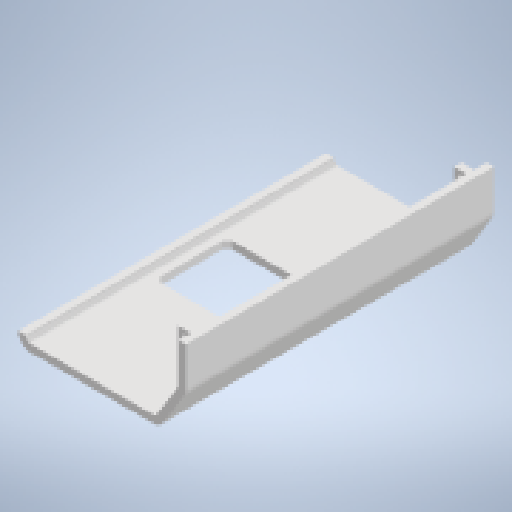
# Autodesk Inventor part: BoxTop3DPrint
Saved by Autodesk Inventor 2025.2 (Build 292293000, 293)
## iProperties
Created: 2025-06-26
Part Number: BoxTop3DPrint
Material: Generic
Document SubType Name: Modeling
Designer: ricoa
Density: 1 g/cm^3
Appearance: Default
Author: ricoa
Autodesk Inventor part; units mm, degrees
ref_plane "YZ Plane" through (0, 0, 0) normal (1, 0, 0) x (0, 1, 0)
ref_plane "XZ Plane" through (0, 0, 0) normal (0, 1, 0) x (-1, 0, 0)
sketch "Sketch1" plane through (0, 0, 0) normal (0, 0, 1) x (1, 0, 0)
  arc A0 (-33.75, -32) -> (-28.75, -37) centre (-28.75, -32) ccw projected
  line L0 (-28.75, -37) -> (20.4614, -37) projected
  line L1 (24.7154, -34.6275) -> (33.004, -21.2078) projected
  arc A1 (20.4614, -37) -> (24.7154, -34.6275) centre (20.4614, -32) ccw projected
  line L2 (33.75, -18.5804) -> (33.75, -3) projected
  arc A2 (33.004, -21.2078) -> (33.75, -18.5804) centre (28.75, -18.5804) ccw projected
  line L3 (30.75, -3) -> (30.75, -18.5804)
  arc A3 (30.4516, -19.6313) -> (30.75, -18.5804) centre (28.75, -18.5804) ccw
  line L4 (30.4516, -19.6313) -> (22.163, -33.051)
  arc A4 (20.4614, -34) -> (22.163, -33.051) centre (20.4614, -32) ccw
  line L5 (20.4614, -34) -> (-28.75, -34)
  arc A5 (-30.75, -32) -> (-28.75, -34) centre (-28.75, -32) ccw
  line L6 (-33.75, -32) -> (-30.75, -32)
  line L7 (30.75, -3) -> (33.75, -3)
  point P0 (0, 0)
  dimension "d0" = 3
  constraints: 10 end point, 7 point on circle, 3 centre point, 1 parallel, 5 other
  measures "d0" radial gap between concentric circles of A1 A4
ref_plane "Work Plane1" through (-33.75, -37, 114) normal (0, 0, -1) x (0, 1, 0)
extrude "Extrusion1" add sketch "Sketch1" along normal up to surface (114 mm away)
sketch "Sketch2" plane through (-28.75, -37, 0) normal (0, -1, 0) x (1, 0, 0)
  line L0 (3.25, 69.1464) -> (3.25, 44.8536) projected
  line L1 (5.1036, 71) -> (3.25, 69.1464) projected
  line L2 (47.3964, 71) -> (5.1036, 71) projected
  line L3 (49.25, 69.1464) -> (47.3964, 71) projected
  line L4 (49.25, 44.8536) -> (49.25, 69.1464) projected
  line L5 (5.1036, 43) -> (47.3964, 43) projected
  line L6 (3.25, 44.8536) -> (5.1036, 43) projected
  line L7 (47.3964, 43) -> (49.25, 44.8536) projected
  line L8 (47.6036, 42.5) -> (4.8964, 42.5)
  line L9 (4.8964, 42.5) -> (2.75, 44.6464)
  line L10 (2.75, 44.6464) -> (2.75, 69.3536)
  line L11 (2.75, 69.3536) -> (4.8964, 71.5)
  line L12 (4.8964, 71.5) -> (47.6036, 71.5)
  line L13 (47.6036, 71.5) -> (49.75, 69.3536)
  line L14 (49.75, 69.3536) -> (49.75, 44.6464)
  line L15 (49.75, 44.6464) -> (47.6036, 42.5)
  point P0 (28.75, 0)
  dimension "d3" = 0.5
  constraints: 16 end point, 7 other
  measures "d3" distance between parallel lines of L5 L8
extrude "Extrusion2" cut sketch "Sketch2" against normal blind 10 contours L1 L2 L3 L4 L7 L5 L6 L0 | L8 L9 L10 L11 L12 L13 L14 L15
sketch "Sketch3" plane through (-28.75, -37, 114) normal (0, 0, 1) x (1, 0, 0)
  line L0 (62.5, 34) -> (59.5, 34) projected
  line L1 (59.5, 34) -> (54.5, 34)
  line L2 (54.5, 34) -> (54.5, 23)
  line L3 (54.5, 23) -> (59.5, 23)
  line L4 (59.5, 23) -> (59.5, 34)
  circle A0 centre (57, 31) radius 1.25 projected
  circle A1 centre (57, 26) radius 1.25 projected
  point P0 (28.75, 37)
  dimension "d6" = 5
  dimension "d7" = 11
  constraints: 8 end point, 2 parallel, 1 horizontal, 1 perpendicular
  measures "d6" distance of L3.end L2.end
  measures "d7" distance of L2.end L1.end
extrude "Extrusion3" add sketch "Sketch3" against normal blind 3
sketch "Sketch4" plane through (0, 0, 0) normal (0, 0, -1) x (-1, 0, 0)
  circle A0 centre (-28.25, -11) radius 1.25 projected
  line L0 (-30.75, -14) -> (-25.75, -14) projected
  line L1 (-25.75, -14) -> (-25.75, -3) projected
  circle A1 centre (-28.25, -6) radius 1.25 projected
  line L2 (33.75, -3) -> (-33.75, -3) projected
  line L3 (-30.75, -3) -> (-30.75, -18.5804) projected
  point P0 (0, 0)
extrude "Extrusion4" add sketch "Sketch4" against normal blind 3
sketch "Sketch5" plane through (0, 0, 0) normal (0, 0, -1) x (-1, 0, 0)
  circle A0 centre (-28.25, -11) radius 1.25 projected
  circle A1 centre (-28.25, -6) radius 1.25 projected
  arc A2 (28.75, -37) -> (33.75, -32) centre (28.75, -32) ccw projected
  line L0 (30.75, -32) -> (33.75, -32) projected
  arc A3 (28.75, -34) -> (30.75, -32) centre (28.75, -32) ccw projected
  line L1 (-20.4614, -34) -> (28.75, -34) projected
  arc A4 (-22.163, -33.051) -> (-20.4614, -34) centre (-20.4614, -32) ccw projected
  line L2 (-30.4516, -19.6313) -> (-22.163, -33.051) projected
  arc A5 (-30.75, -18.5804) -> (-30.4516, -19.6313) centre (-28.75, -18.5804) ccw projected
  line L3 (-30.75, -14) -> (-30.75, -18.5804) projected
  line L4 (-30.75, -14) -> (-25.75, -14) projected
  line L5 (-25.75, -14) -> (-25.75, -3) projected
  line L6 (-33.75, -3) -> (-25.75, -3) projected
  line L7 (-33.75, -18.5804) -> (-33.75, -3) projected
  arc A6 (-33.75, -18.5804) -> (-33.004, -21.2078) centre (-28.75, -18.5804) ccw projected
  line L8 (-24.7154, -34.6275) -> (-33.004, -21.2078) projected
  arc A7 (-24.7154, -34.6275) -> (-20.4614, -37) centre (-20.4614, -32) ccw projected
  line L9 (28.75, -37) -> (-20.4614, -37) projected
  line L10 (-30.75, -3) -> (-30.75, -18.5804) projected
  point P0 (0, 0)
extrude "Extrusion5" add sketch "Sketch5" along normal blind 5 contours L9 A7 L8 A6 L7 L6 L10 L3 A5 L2 A4 L1 A3 L0 A2
sketch "Sketch6" plane through (-28.75, -37, 114) normal (0, 0, 1) x (1, 0, 0)
  circle A0 centre (57, 26) radius 1.25 projected
  circle A1 centre (57, 31) radius 1.25 projected
  line L0 (-2, 5) -> (-5, 5) projected
  arc A2 (-5, 5) -> (0, 0) centre (0, 5) ccw projected
  line L1 (0, 0) -> (49.2114, 0) projected
  arc A3 (49.2114, 0) -> (53.4654, 2.3725) centre (49.2114, 5) ccw projected
  line L2 (53.4654, 2.3725) -> (61.754, 15.7922) projected
  arc A4 (61.754, 15.7922) -> (62.5, 18.4196) centre (57.5, 18.4196) ccw projected
  line L3 (62.5, 18.4196) -> (62.5, 34) projected
  line L4 (62.5, 34) -> (54.5, 34) projected
  line L5 (54.5, 34) -> (54.5, 23) projected
  line L6 (54.5, 23) -> (59.5, 23) projected
  line L7 (59.5, 23) -> (59.5, 18.4196) projected
  arc A5 (59.2016, 17.3687) -> (59.5, 18.4196) centre (57.5, 18.4196) ccw projected
  line L8 (59.2016, 17.3687) -> (50.913, 3.949) projected
  arc A6 (49.2114, 3) -> (50.913, 3.949) centre (49.2114, 5) ccw projected
  line L9 (49.2114, 3) -> (0, 3) projected
  arc A7 (-2, 5) -> (0, 3) centre (0, 5) ccw projected
  line L10 (59.5, 18.4196) -> (59.5, 34) projected
  point P0 (28.75, 37)
extrude "Extrusion6" add sketch "Sketch6" along normal blind 5 contours A7 L9 A6 L8 A5 L7 L10 L4 L3 A4 L2 A3 L1 A2 L0
sketch "Sketch7" plane through (-23.8536, -37, 42.5) normal (0, -1, 0) x (1, 0, 0)
  point P0 (23.8536, -42.5)
body "Solid1"
